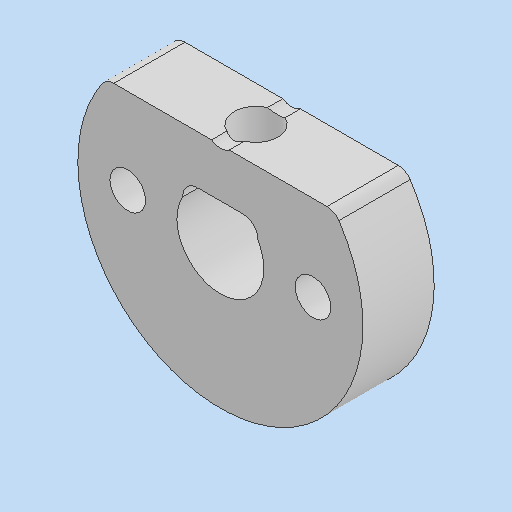
# Autodesk Inventor part: AP5.0_D-fix-A
Saved by Autodesk Inventor 2025.3 (Build 293356030, 356C)
## iProperties
Created: 2025-05-21
Part Number: AP5.0_D-fix-A
Material: 一般
Document SubType Name: Sheet Metal
Designer: 8326d
Density: 1 g/cm^3
Sheet Metal Rule: Default_mm
Appearance: 既定
Author: 8326d
Autodesk Inventor part; units mm, degrees
ref_plane "YZ Plane" through (0, 0, 0) normal (1, 0, 0) x (0, 1, 0)
ref_plane "XZ Plane" through (0, 0, 0) normal (0, 1, 0) x (-1, 0, 0)
ref_plane "XY Plane" through (0, 0, 0) normal (0, 0, 1) x (1, 0, 0)
sketch "スケッチ1" plane through (0, 0, 0) normal (0, 0, 1) x (1, 0, 0)
  circle A0 centre (0, 0) radius 10
  circle A1 centre (0, 0) radius 3.05
  line L0 (-8, 6) -> (8, 6)
  line L1 (-1.5945, 2.6) -> (1.5945, 2.6)
  line L2 (-1.5945, 2.6) -> (1.5945, 2.6) construction
  point P0 (0.9447, 2.9)
  point P1 (-0.9447, 2.9)
  dimension "d0" = 20
  dimension "d1" = 6.1
  dimension "d2" = 6
  dimension "d20" = 0
  dimension "d21" = 2.6
  measures "d0" diameter of A0
  measures "d1" diameter of A1
  measures "d2" distance from line of point (0, 0) L0
  measures "d20" distance between parallel lines of L1 L2
  measures "d21" distance from line of point (0, 0) L1
extrude "プレート1" add sketch "スケッチ1" along normal blind 5 contours A0 L0 | L1 A1 picked at (-0.1116, 5.0105) picked at (0.1116, 2.7439)
sketch "スケッチ2" plane through (0, 0, 0) normal (0, 0, -1) x (-1, 0, 0)
  line L0 (-6.5, 0) -> (6.5, 0) construction
  point P0 (0, 0)
  point P1 (0, 0)
  dimension "d4" = 13
  constraints: 3 coincident, 2 end point, 1 horizontal, 1 midpoint
  measures "d4" distance of L0.start L0.end
hole "穴1" at (6.5, 0, 0) at (-6.5, 0, 0) direction (0, 0, 1) diameter 2.5 end through all
sketch "スケッチ5" plane through (0, 0, 5) normal (0, 0, 1) x (1, 0, 0)
  arc A0 (-1.5945, 2.6) -> (1.5945, 2.6) centre (0, 0) ccw projected
  circle A1 centre (-1.5945, 1.55) radius 1.05
  circle A2 centre (1.5945, 1.55) radius 1.05
  point P0 (2.6441, 1.5203)
  point P1 (-2.6441, 1.5203)
  dimension "d22" = 2.1
  dimension "d23" = 2.1
  constraints: 2 vertical alignment, 6 other
extrude "押し出し3" cut sketch "スケッチ5" against normal through all contours A0 A2 | A0 A1 picked at (2.2581, 2.1473) picked at (-2.2616, 2.1428)
sketch "スケッチ6" plane through (0, 0, 5) normal (0, 0, 1) x (1, 0, 0)
  line L0 (-8, 6) -> (8, 6) projected
  circle A0 centre (0, 6.85) radius 1.05
  point P0 (0, 0)
  dimension "d26" = 2.1
  dimension "d27" = 0.85
  constraints: 1 centre point, 1 vertical alignment
  measures "d26" diameter of A0
  measures "d27" distance from line of L0 A0.centre
extrude "押し出し4" cut sketch "スケッチ6" against normal through all
fillet "フィレット2" radius 1 2 edges at (8, 6, 2.5) (-8, 6, 2.5)
sketch "スケッチ7" plane through (-0.6164, 6, 5) normal (0, 1, 0) x (1, 0, 0)
  line L0 (0, 0) -> (0, 5) projected
  line L1 (1.2329, 0) -> (0, 0) projected
  line L2 (1.2329, 5) -> (1.2329, 0) projected
  line L3 (0, 5) -> (1.2329, 5) projected
  line L4 (1.2329, 2.5) -> (0, 2.5) construction
  point P0 (0.6164, 5)
  point P1 (0.6164, 2.5)
  point P2 (0.6164, 2.5)
  constraints: 3 midpoint, 2 end point, 1 coincident
hole "穴2" at (0, 6, 2.5) direction (0, -1, 0) diameter 3.1 depth 5 tip angle 118
equation "\"d10\" = Thickness"
equation "\"d23\" = d22"
equation "\"d36\" = Thickness"
equation "\"d3\" = Thickness"
equation "\"BendRadius\" = Thickness"
equation "\"BendReliefWidth\" = Thickness"
equation "\"BendReliefDepth\" = 0.5 * Thickness"
equation "\"TransitionRadius\" = BendRadius"
equation "\"JacobiRadiusSize\" = BendRadius"
equation "\"GapSize\" = Thickness"
equation "\"Thickness\" = 5"
